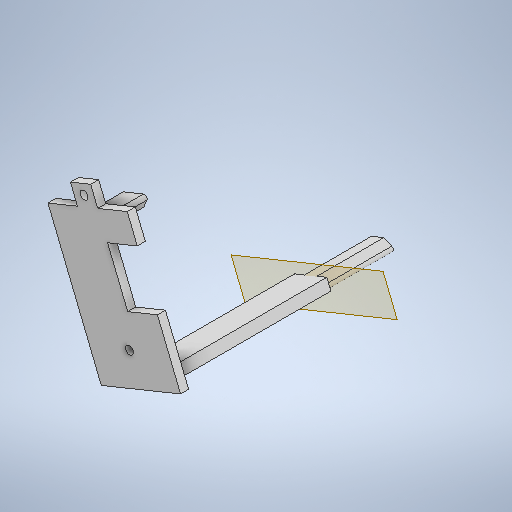
# Autodesk Inventor part: Support_base
Saved by Autodesk Inventor 2025 (Build 290162000, 162)
## iProperties
Created: 2026-10-27
Part Number: Support_base
Material: Generic
Document SubType Name: Modeling
Designer: diego
Density: 1 g/cm^3
Appearance: Default
Author: diego
Autodesk Inventor part; units mm, degrees
ref_plane "YZ Plane" through (0, 0, 0) normal (1, 0, 0) x (0, 1, 0)
ref_plane "XZ Plane" through (0, 0, 0) normal (0, 1, 0) x (-1, 0, 0)
ref_plane "Work Plane1" through (0.6497, -10.1379, 0) normal (0, 0, 1) x (-0.9265, -0.3764, 0)
sketch "Sketch1" plane through (0.6497, -10.1379, 0) normal (0, 0, 1) x (-0.9265, -0.3764, 0)
  line L0 (-4.7946, -9.7818) -> (-7.0875, -7.4889) projected
  arc A0 (-6.3804, -5.7818) -> (-7.0875, -7.4889) centre (-6.3804, -6.7818) ccw projected
  line L1 (-6.3804, -5.7818) -> (1.7912, -5.7818) projected
  arc A1 (2.4983, -7.4889) -> (1.7912, -5.7818) centre (1.7912, -6.7818) ccw projected
  line L2 (2.4983, -7.4889) -> (0.2054, -9.7818) projected
  line L3 (0.2054, -9.7818) -> (27.5974, -9.7818) projected
  line L4 (22.5231, -7.9349) -> (27.5974, -9.7818) projected
  line L5 (22.5231, -7.9349) -> (0.3437, 0.1378) projected
  line L6 (-5.3114, 0) -> (-3.214, 0) projected
  line L7 (-5.3114, 0) -> (-27.1123, -7.9349) projected
  line L8 (-32.1866, -9.7818) -> (-27.1123, -7.9349) projected
  line L9 (-32.1866, -9.7818) -> (-4.7946, -9.7818) projected
  line L10 (-7.0875, -7.4889) -> (-4.7946, -9.7818)
  line L11 (-4.7946, -9.7818) -> (-32.1866, -9.7818)
  line L12 (-32.1866, -9.7818) -> (-27.1123, -7.9349)
  line L13 (-27.1123, -7.9349) -> (-5.3114, 0)
  line L14 (-5.3114, 0) -> (0.7222, 0)
  line L15 (0.7222, 0) -> (22.5231, -7.9349)
  line L16 (22.5231, -7.9349) -> (27.5974, -9.7818)
  line L17 (27.5974, -9.7818) -> (0.2054, -9.7818)
  line L18 (0.2054, -9.7818) -> (2.4983, -7.4889)
  arc A2 (2.4983, -7.4889) -> (1.7912, -5.7818) centre (1.7912, -6.7818) ccw
  line L19 (1.7912, -5.7818) -> (-6.3804, -5.7818)
  arc A3 (-6.3804, -5.7818) -> (-7.0875, -7.4889) centre (-6.3804, -6.7818) ccw
  line L20 (0.2054, -9.7818) -> (-4.7946, -9.7818)
  point P0 (-3.214, -9.6369)
  dimension "d0" = 0
  constraints: 22 end point, 4 point on circle, 2 centre point, 1 horizontal, 11 other
  measures "d0" distance between parallel lines of L0 L10
extrude "Extrusion1" add sketch "Sketch1" along normal blind 65 contours L0 A0 L1 A1 L2 L20
sketch "Sketch3" plane through (0.6497, -10.1379, 0) normal (0, 0, -1) x (0.9265, 0.3764, 0)
  arc A0 (-1.7912, -5.7818) -> (-2.4983, -7.4889) centre (-1.7912, -6.7818) ccw projected
  line L0 (-0.2054, -9.7818) -> (-2.4983, -7.4889) projected
  line L1 (4.7946, -9.7818) -> (-0.2054, -9.7818) projected
  line L2 (7.0875, -7.4889) -> (4.7946, -9.7818) projected
  arc A1 (7.0875, -7.4889) -> (6.3804, -5.7818) centre (6.3804, -6.7818) ccw projected
  line L3 (-1.7912, -5.7818) -> (6.3804, -5.7818) projected
  point P0 (3.214, -9.6369)
extrude "Extrusion2" add sketch "Sketch3" along normal blind 30
sketch "Sketch4" plane through (0.6497, -10.1379, 65) normal (0, 0, 1) x (-0.9265, -0.3764, 0)
  arc A0 (2.4983, -7.4889) -> (1.7912, -5.7818) centre (1.7912, -6.7818) ccw projected
  line L0 (1.7912, -5.7818) -> (-6.3804, -5.7818) projected
  arc A1 (-6.3804, -5.7818) -> (-7.0875, -7.4889) centre (-6.3804, -6.7818) ccw projected
  line L1 (-7.0875, -7.4889) -> (-4.7946, -9.7818) projected
  line L2 (-4.7946, -9.7818) -> (0.2054, -9.7818) projected
  line L3 (0.2054, -9.7818) -> (2.4983, -7.4889) projected
  line L4 (1.7912, -5.7818) -> (-6.3804, -5.7818) projected
  line L5 (-2.2946, -5.7818) -> (-2.2946, -9.7818)
  line L6 (17.7054, -0.7818) -> (-22.2946, -0.7818)
  line L7 (-22.2946, -0.7818) -> (-22.2946, -23.7818)
  line L8 (-22.2946, -23.7818) -> (17.7054, -23.7818)
  line L9 (17.7054, -23.7818) -> (17.7054, -0.7818)
  line L10 (-2.2946, -0.7818) -> (-2.2946, -23.7818) construction
  line L11 (0.2054, -9.7818) -> (-4.7946, -9.7818) projected
  line L12 (-18.2946, -0.7818) -> (13.7054, -0.7818)
  line L13 (-18.2946, -0.7818) -> (-18.2946, -15.7818) construction
  line L14 (-18.2946, -15.7818) -> (-22.2946, -15.7818)
  line L15 (-18.2946, -0.7818) -> (-22.2946, -15.7818)
  line L16 (13.7054, -0.7818) -> (17.7054, -15.7818)
  point P0 (-3.214, -9.6369)
  point P1 (-2.2946, -9.7818)
  point P2 (17.7054, -15.7818)
  point P3 (13.7054, -0.7818)
  point P4 (-18.2946, -0.7818)
  dimension "d5" = 40
  dimension "d6" = 5
  dimension "d13" = 14
  dimension "d14" = 32
  dimension "d15" = 15
  constraints: 22 end point, 6 midpoint, 2 horizontal, 2 parallel, 2 perpendicular, 2 point on line, 1 symmetric about line, 1 vertical
  measures "d5" distance of L8.end L7.end
  measures "d6" distance between parallel lines of L0 L6
  measures "d13" distance between parallel lines of L8 L2
  measures "d14" distance of L12.start L12.end
  measures "d15" distance of L12.start L13.end
extrude "Extrusion3" add sketch "Sketch4" against normal blind 3 contours L16 L9 L8 L7 L15 L6
sketch "Sketch5" plane through (0.6497, -10.1379, 62) normal (0, 0, -1) x (0.9265, 0.3764, 0)
  line L0 (22.2946, -23.7818) -> (22.2946, -15.7818) projected
  line L1 (18.2946, -0.7818) -> (-13.7054, -0.7818) projected
  line L2 (-17.7054, -15.7818) -> (-17.7054, -23.7818) projected
  line L3 (-17.7054, -23.7818) -> (22.2946, -23.7818) projected
  arc A0 (-1.7912, -5.7818) -> (-2.4983, -7.4889) centre (-1.7912, -6.7818) ccw projected
  line L4 (6.3804, -5.7818) -> (-1.7912, -5.7818) projected
  arc A1 (7.0875, -7.4889) -> (6.3804, -5.7818) centre (6.3804, -6.7818) ccw projected
  line L5 (4.7946, -9.7818) -> (7.0875, -7.4889) projected
  line L6 (-0.2054, -9.7818) -> (4.7946, -9.7818) projected
  line L7 (-2.4983, -7.4889) -> (-0.2054, -9.7818) projected
  line L8 (-4.2054, -5.7818) -> (8.7946, -5.7818)
  line L9 (8.7946, -5.7818) -> (8.7946, -9.7818)
  line L10 (8.7946, -9.7818) -> (-4.2054, -9.7818)
  line L11 (-4.2054, -9.7818) -> (-4.2054, -5.7818)
  line L12 (-4.2054, -5.7818) -> (8.7946, -9.7818) construction
  line L13 (8.7946, -5.7818) -> (-4.2054, -9.7818) construction
  line L14 (-2.4983, -7.4889) -> (-0.2054, -9.7818) projected
  line L15 (-0.2054, -9.7818) -> (-4.2054, -5.7818)
  line L16 (4.7946, -9.7818) -> (8.7946, -5.7818)
  line L17 (22.2946, -15.7818) -> (18.2946, -0.7818) projected
  line L18 (-13.7054, -0.7818) -> (-17.7054, -15.7818) projected
  point P0 (3.214, -9.6369)
  point P1 (2.2946, -7.7818)
  point P2 (2.2946, -9.7818)
  point P3 (2.2946, -5.7818)
  point P4 (-0.2054, -9.7818)
  point P5 (4.7946, -9.7818)
  point P6 (6.3804, -5.7818)
  point P7 (-1.7912, -5.7818)
  constraints: 16 end point, 6 midpoint, 5 point on line, 2 parallel, 1 horizontal, 1 perpendicular, 1 tangent
ref_plane "Work Plane2" through (-30.1843, -12.7613, 0) normal (0, 0, 1) x (1, 0, 0)
extrude "Extrusion4" add sketch "Sketch5" along normal up to surface (62 mm away) contours L4 A1 L5 L6 L7 A0 | A0 L15 L8 | L7 L10 L11 L15 | L8 L16 A1 | L16 L9 L10 L5
sketch "Sketch6" plane through (0.6497, -10.1379, -30) normal (0, 0, -1) x (0.9265, 0.3764, 0)
  line L0 (6.3804, -5.7818) -> (-1.7912, -5.7818) projected
  arc A0 (-1.7912, -5.7818) -> (-2.4983, -7.4889) centre (-1.7912, -6.7818) ccw projected
  line L1 (-2.4983, -7.4889) -> (-0.2054, -9.7818) projected
  line L2 (-0.2054, -9.7818) -> (4.7946, -9.7818) projected
  line L3 (4.7946, -9.7818) -> (7.0875, -7.4889) projected
  arc A1 (7.0875, -7.4889) -> (6.3804, -5.7818) centre (6.3804, -6.7818) ccw projected
  point P0 (3.214, -9.6369)
extrude "Extrusion5" cut sketch "Sketch6" against normal blind 5
sketch "Sketch7" plane through (0.6497, -10.1379, 62) normal (0, 0, -1) x (0.9265, 0.3764, 0)
  line L0 (8.7946, -9.7818) -> (-4.2054, -9.7818) projected
  line L1 (-1.7912, -5.7818) -> (6.3804, -5.7818) projected
  line L2 (8.7946, -5.7818) -> (6.3804, -5.7818) projected
  line L3 (8.7946, -5.7818) -> (-4.2054, -5.7818) projected
  line L4 (-1.7912, -5.7818) -> (-4.2054, -5.7818) projected
  line L5 (8.7946, -5.7818) -> (-4.2054, -5.7818) projected
  line L6 (8.7946, -5.7818) -> (8.7946, -9.7818) projected
  line L7 (8.7946, -9.7818) -> (-4.2054, -9.7818) projected
  line L8 (-4.2054, -9.7818) -> (-4.2054, -5.7818) projected
  line L9 (-17.7054, -15.7818) -> (-17.7054, -23.7818) projected
  line L10 (-17.7054, -23.7818) -> (22.2946, -23.7818) projected
  line L11 (22.2946, -23.7818) -> (22.2946, -15.7818) projected
  line L12 (22.2946, -15.7818) -> (18.2946, -0.7818) projected
  line L13 (18.2946, -0.7818) -> (-13.7054, -0.7818) projected
  line L14 (-13.7054, -0.7818) -> (-17.7054, -15.7818) projected
  line L15 (-4.2054, -5.7818) -> (8.7946, -5.7818)
  line L16 (8.7946, -5.7818) -> (8.7946, -0.7818)
  line L17 (8.7946, -0.7818) -> (-4.2054, -0.7818)
  line L18 (-4.2054, -0.7818) -> (-4.2054, -5.7818)
  line L19 (5.8653, -0.7818) -> (-1.2761, -0.7818)
  line L20 (-1.2761, -5.7818) -> (5.8653, -5.7818)
  line L21 (2.2946, -0.7818) -> (2.2946, -5.7818)
  line L22 (-1.2054, -0.7818) -> (5.7946, -0.7818)
  line L23 (5.7946, -0.7818) -> (5.7946, -5.7818)
  line L24 (5.7946, -5.7818) -> (-1.2054, -5.7818)
  line L25 (-1.2054, -5.7818) -> (-1.2054, -0.7818)
  line L26 (-1.2054, -0.7818) -> (5.7946, -5.7818) construction
  line L27 (5.7946, -0.7818) -> (-1.2054, -5.7818) construction
  point P0 (3.214, -9.6369)
  point P1 (2.2946, -3.2818)
  point P2 (5.7946, -0.7818)
  point P3 (5.7946, -5.7818)
  point P4 (6.3804, -5.7818)
  point P5 (-1.2054, -5.7818)
  point P6 (-1.2054, -0.7818)
  point P7 (-4.2054, -0.7818)
  point P8 (-4.2054, -5.7818)
  point P9 (-1.7912, -5.7818)
  dimension "d16" = 3
  constraints: 26 end point, 6 midpoint, 6 point on line, 5 parallel, 3 horizontal, 2 perpendicular, 1 vertical
  measures "d16" distance between parallel lines of L23 L16
extrude "Extrusion6" add sketch "Sketch7" along normal blind 5 contours L2 L1 L23 L13 L16 | L18 L13 L25 L1 L3
sketch "Sketch8" plane through (-6.9283, -2.6585, 62) normal (-0.9265, -0.3764, 0) x (0, 0, -1)
  line L0 (62, 4) -> (62, 0) projected
  line L1 (5, 4) -> (62, 4) projected
  line L2 (5, 9) -> (5, 4) projected
  line L3 (0, 9) -> (5, 9) projected
  line L4 (0, 0) -> (0, 9) projected
  line L5 (0, 0) -> (62, 0) projected
  line L6 (5, 4) -> (0, 9)
  point P0 (62, 0.1449)
  constraints: 2 end point
extrude "Extrusion7" cut sketch "Sketch8" against normal through all contours L6 L3 L2
sketch "Sketch9" plane through (0.6497, -10.1379, 65) normal (0, 0, 1) x (-0.9265, -0.3764, 0)
  line L0 (17.7054, -23.7818) -> (17.7054, -15.7818) projected
  line L1 (17.7054, -15.7818) -> (13.7054, -0.7818) projected
  line L2 (13.7054, -0.7818) -> (-18.2946, -0.7818) projected
  line L3 (-18.2946, -0.7818) -> (-22.2946, -15.7818) projected
  line L4 (-22.2946, -15.7818) -> (-22.2946, -23.7818) projected
  line L5 (-22.2946, -23.7818) -> (17.7054, -23.7818) projected
  line L6 (13.7054, -0.7818) -> (13.7054, -23.7818)
  line L7 (-18.2946, -0.7818) -> (-18.2946, -23.7818)
  point P0 (-3.214, -9.6369)
  constraints: 4 end point, 2 point on line, 1 perpendicular, 1 vertical
extrude "Extrusion8" cut sketch "Sketch9" against normal blind 65 contours L5 L6 L1 L0 | L5 L4 L3 L7
sketch "Sketch10" plane through (0.6497, -10.1379, 65) normal (0, 0, 1) x (0.9265, 0.3764, 0)
  line L0 (5.7946, 5.7818) -> (5.7946, 0.7818) construction
  line L1 (5.7946, 0.7818) -> (-1.2054, 0.7818) construction
  line L2 (-1.2054, 0.7818) -> (-1.2054, 5.7818) construction
  line L3 (5.7946, 5.7818) -> (-1.2054, 5.7818) construction
  line L4 (5.7946, 5.7818) -> (-1.2054, 5.7818) construction
  line L5 (-1.2054, 5.7818) -> (-4.2054, 5.7818) construction
  line L6 (-1.7912, 5.7818) -> (-4.2054, 5.7818) construction
  line L7 (-1.7912, 5.7818) -> (6.3804, 5.7818) construction
  line L8 (8.7946, 5.7818) -> (6.3804, 5.7818) construction
  line L9 (8.7946, 5.7818) -> (5.7946, 5.7818) construction
  line L10 (18.2946, 23.7818) -> (18.2946, 0.7818) construction
  line L11 (18.2946, 0.7818) -> (8.7946, 0.7818) construction
  line L12 (8.7946, 0.7818) -> (8.7946, 9.7818) construction
  line L13 (8.7946, 9.7818) -> (-4.2054, 9.7818) construction
  line L14 (-4.2054, 9.7818) -> (-4.2054, 0.7818) construction
  line L15 (-4.2054, 0.7818) -> (-13.7054, 0.7818) construction
  line L16 (-13.7054, 0.7818) -> (-13.7054, 23.7818) construction
  line L17 (-13.7054, 23.7818) -> (18.2946, 23.7818) construction
  line L18 (8.7946, 5.7818) -> (18.2946, 5.7818) construction
  line L19 (-4.2054, 5.7818) -> (-13.7054, 5.7818) construction
  line L20 (18.2946, 0.7818) -> (18.2946, 23.7818) projected
  line L21 (18.2946, 23.7818) -> (-13.7054, 23.7818) projected
  line L22 (-13.7054, 23.7818) -> (-13.7054, 0.7818) projected
  line L23 (-13.7054, 0.7818) -> (18.2946, 0.7818) projected
  line L24 (18.2946, 5.7818) -> (-13.7054, 5.7818)
  point P0 (3.214, 9.6369)
  point P1 (18.2946, 5.7818)
  point P2 (-13.7054, 5.7818)
  constraints: 6 end point, 3 point on line, 1 collinear, 1 perpendicular
extrude "Extrusion9" cut sketch "Sketch10" against normal blind 65 contours L23 L22 L24 L20
sketch "Sketch12" plane through (0.6497, -10.1379, 65) normal (0, 0, 1) x (0.9265, 0.3764, 0)
  line L0 (-13.7054, 5.7818) -> (18.2946, 5.7818) projected
  line L1 (18.2946, 5.7818) -> (18.2946, 23.7818) projected
  line L2 (18.2946, 23.7818) -> (-13.7054, 23.7818) projected
  line L3 (-13.7054, 23.7818) -> (-13.7054, 5.7818) projected
  line L4 (-13.7054, 14.7818) -> (18.2946, 14.7818) construction
  line L5 (18.2946, 23.7818) -> (18.2946, 5.7818) projected
  line L6 (-13.7054, 5.7818) -> (18.2946, 5.7818) projected
  line L7 (2.2946, 5.7818) -> (2.2946, 23.7818) construction
  line L8 (2.2946, 5.7818) -> (2.2946, 53.7818) construction
  line L9 (18.2946, 5.7818) -> (-13.7054, 5.7818)
  line L10 (-13.7054, 5.7818) -> (-13.7054, 53.7818)
  line L11 (-13.7054, 53.7818) -> (18.2946, 53.7818)
  line L12 (18.2946, 53.7818) -> (18.2946, 5.7818)
  line L13 (-13.7054, 53.7818) -> (18.2946, 53.7818)
  line L14 (18.2946, 53.7818) -> (18.2946, 58.7818)
  line L15 (18.2946, 58.7818) -> (-13.7054, 58.7818)
  line L16 (-13.7054, 58.7818) -> (-13.7054, 53.7818)
  dimension "d25" = 48
  dimension "d26" = 5
  constraints: 22 end point, 5 midpoint, 5 parallel, 2 horizontal, 2 perpendicular, 1 point on line, 1 vertical
  measures "d25" distance of L7.start L8.end
  measures "d26" distance of L15.end L10.end
extrude "Extrusion10" add sketch "Sketch12" against normal up to surface (3 mm away) contours L10 L11 L12 L2 | L16 L15 L14 L11
sketch "Sketch13" plane through (0.6497, -10.1379, 62) normal (0, 0, -1) x (-0.9265, -0.3764, 0)
  line L0 (4.2054, 5.7818) -> (13.7054, 5.7818) projected
  line L1 (13.7054, 5.7818) -> (13.7054, 58.7818) projected
  line L2 (13.7054, 58.7818) -> (-18.2946, 58.7818) projected
  line L3 (-18.2946, 58.7818) -> (-18.2946, 5.7818) projected
  line L4 (-18.2946, 5.7818) -> (-8.7946, 5.7818) projected
  line L5 (-8.7946, 5.7818) -> (-8.7946, 9.7818) projected
  line L6 (-8.7946, 9.7818) -> (4.2054, 9.7818) projected
  line L7 (4.2054, 9.7818) -> (4.2054, 5.7818) projected
  line L8 (-18.2946, 58.7818) -> (13.7054, 58.7818)
  line L9 (13.7054, 58.7818) -> (13.7054, 55.7818)
  line L10 (1.7912, 55.7818) -> (-18.2946, 55.7818)
  line L11 (-18.2946, 55.7818) -> (-18.2946, 58.7818)
  line L12 (-18.2946, 55.7818) -> (13.7054, 55.7818)
  line L13 (13.7054, 55.7818) -> (13.7054, 51.7818)
  line L14 (13.7054, 51.7818) -> (-18.2946, 51.7818)
  line L15 (-18.2946, 51.7818) -> (-18.2946, 55.7818)
  line L16 (-2.2946, 51.7818) -> (-2.2946, 58.7818) construction
  line L17 (0.2054, 51.7818) -> (-4.7946, 51.7818)
  line L18 (-4.7946, 51.7818) -> (-4.7946, 55.7818)
  line L19 (-4.7946, 55.7818) -> (0.2054, 55.7818)
  line L20 (0.2054, 55.7818) -> (0.2054, 51.7818)
  line L21 (0.2054, 51.7818) -> (-4.7946, 55.7818) construction
  line L22 (-4.7946, 51.7818) -> (0.2054, 55.7818) construction
  line L23 (-4.7946, 51.7818) -> (-7.0875, 54.0747)
  line L24 (-4.7946, 51.7818) -> (-1.552, 51.7818) construction
  line L25 (0.2054, 51.7818) -> (2.4983, 54.0747)
  line L26 (0.2054, 51.7818) -> (3.448, 51.7818) construction
  line L27 (-6.3804, 55.7818) -> (4.2054, 55.7818)
  arc A0 (-6.3804, 55.7818) -> (-7.0875, 54.0747) centre (-6.3804, 54.7818) ccw
  arc A1 (2.4983, 54.0747) -> (1.7912, 55.7818) centre (1.7912, 54.7818) ccw
  point P0 (-3.214, 9.6369)
  point P1 (-2.2946, 53.7818)
  point P2 (-8.7946, 55.7818)
  point P3 (-4.7946, 51.7818)
  point P4 (0.2054, 51.7818)
  dimension "d29" = 3
  dimension "d30" = 4
  dimension "d31" = 5
  dimension "d32" = 2
  dimension "d33" = 135
  dimension "d34" = 45
  dimension "d35" = 1
  constraints: 40 end point, 11 point on line, 6 parallel, 5 horizontal, 5 midpoint, 4 perpendicular, 4 point on circle, 4 tangent, 2 centre point, 2 equal length, 1 collinear, 1 equal radius
  measures "d29" distance between parallel lines of L2 L10
  measures "d30" distance between parallel lines of L10 L14
  measures "d31" distance of L18.end L19.end
  measures "d32" distance from line of L10 point (-2.295, 53.782)
  measures "d33" angle of L24 L23
  measures "d34" angle of L26 L25
  measures "d35" radius of A0
extrude "Extrusion11" add sketch "Sketch13" along normal blind 13 contours L14 L18 L10 L20 | L20 L10 A1 L25 | L23 A0 L10 L18
sketch "Sketch14" plane through (0.6497, -10.1379, 62) normal (0, 0, -1) x (-0.9265, -0.3764, 0)
  arc A0 (2.4983, 54.0747) -> (1.7912, 55.7818) centre (1.7912, 54.7818) ccw projected
  line L0 (2.4983, 54.0747) -> (0.2054, 51.7818) projected
  line L1 (0.2054, 51.7818) -> (-4.7946, 51.7818) projected
  line L2 (-4.7946, 51.7818) -> (-7.0875, 54.0747) projected
  arc A1 (-6.3804, 55.7818) -> (-7.0875, 54.0747) centre (-6.3804, 54.7818) ccw projected
  line L3 (-6.3804, 55.7818) -> (1.7912, 55.7818) projected
  line L4 (4.2054, 5.7818) -> (13.7054, 5.7818) projected
  line L5 (13.7054, 5.7818) -> (13.7054, 58.7818) projected
  line L6 (13.7054, 58.7818) -> (-18.2946, 58.7818) projected
  line L7 (-18.2946, 58.7818) -> (-18.2946, 5.7818) projected
  line L8 (-18.2946, 5.7818) -> (-8.7946, 5.7818) projected
  line L9 (-8.7946, 5.7818) -> (-8.7946, 9.7818) projected
  line L10 (-8.7946, 9.7818) -> (4.2054, 9.7818) projected
  line L11 (4.2054, 9.7818) -> (4.2054, 5.7818) projected
  line L12 (1.7912, 5.7818) -> (-6.3804, 5.7818) projected
  line L13 (-2.2946, 5.7818) -> (-2.2946, 65.7818) construction
  line L14 (-6.3804, 55.7818) -> (1.7912, 55.7818)
  line L15 (1.7912, 55.7818) -> (1.7912, 65.7818)
  line L16 (1.7912, 65.7818) -> (-6.3804, 65.7818)
  line L17 (-6.3804, 65.7818) -> (-6.3804, 55.7818)
  point P0 (-3.214, 9.6369)
  point P1 (-6.3804, 58.7818)
  point P2 (1.7912, 58.7818)
  dimension "d38" = 60
  constraints: 10 end point, 3 point on line, 2 midpoint, 2 parallel, 1 horizontal, 1 perpendicular, 1 vertical
  measures "d38" distance of L13.start L13.end
extrude "Extrusion12" add sketch "Sketch14" against normal up to surface (3 mm away) contours L6 L17 L16 L15
sketch "Sketch15" plane through (0.6497, -10.1379, 62) normal (0, 0, -1) x (-0.9265, -0.3764, 0)
  arc A0 (2.4983, 54.0747) -> (1.7912, 55.7818) centre (1.7912, 54.7818) ccw projected
  line L0 (2.4983, 54.0747) -> (0.2054, 51.7818) projected
  line L1 (0.2054, 51.7818) -> (-4.7946, 51.7818) projected
  line L2 (-4.7946, 51.7818) -> (-7.0875, 54.0747) projected
  arc A1 (-6.3804, 55.7818) -> (-7.0875, 54.0747) centre (-6.3804, 54.7818) ccw projected
  line L3 (-6.3804, 55.7818) -> (1.7912, 55.7818) projected
  line L4 (4.2054, 5.7818) -> (13.7054, 5.7818) projected
  line L5 (13.7054, 5.7818) -> (13.7054, 58.7818) projected
  line L6 (13.7054, 58.7818) -> (1.7912, 58.7818) projected
  line L7 (1.7912, 58.7818) -> (1.7912, 65.7818) projected
  line L8 (1.7912, 65.7818) -> (-6.3804, 65.7818) projected
  line L9 (-6.3804, 65.7818) -> (-6.3804, 58.7818) projected
  line L10 (-6.3804, 58.7818) -> (-18.2946, 58.7818) projected
  line L11 (-18.2946, 58.7818) -> (-18.2946, 5.7818) projected
  line L12 (-18.2946, 5.7818) -> (-8.7946, 5.7818) projected
  line L13 (-8.7946, 5.7818) -> (-8.7946, 9.7818) projected
  line L14 (-8.7946, 9.7818) -> (4.2054, 9.7818) projected
  line L15 (4.2054, 9.7818) -> (4.2054, 5.7818) projected
  line L16 (-2.2946, 65.7818) -> (-2.2946, 5.7818) construction
  line L17 (13.7054, 5.7818) -> (-18.2946, 5.7818) projected
  circle A2 centre (-2.2946, 62.2818) radius 1.5
  circle A3 centre (-2.2946, 17.2818) radius 1.5
  line L18 (-6.3804, 58.7818) -> (1.7912, 65.7818) construction
  line L19 (-6.3804, 65.7818) -> (1.7912, 58.7818) construction
  point P0 (-3.214, 9.6369)
  dimension "d41" = 3
  dimension "d42" = 3
  dimension "d43" = 45
  constraints: 6 end point, 3 midpoint, 2 centre point, 2 point on line
  measures "d41" diameter of A2
  measures "d42" diameter of A3
  measures "d43" distance of A2.centre A3.centre
extrude "Extrusion13" cut sketch "Sketch15" against normal blind 10 contours A2 | A3
sketch "Sketch16" plane through (0.6497, -10.1379, 62) normal (0, 0, -1) x (-0.9265, -0.3764, 0)
  circle A0 centre (-2.2946, 62.2818) radius 1.5 projected
  circle A1 centre (-2.2946, 17.2818) radius 1.5 projected
  arc A2 (2.4983, 54.0747) -> (1.7912, 55.7818) centre (1.7912, 54.7818) ccw projected
  line L0 (2.4983, 54.0747) -> (0.2054, 51.7818) projected
  line L1 (0.2054, 51.7818) -> (-4.7946, 51.7818) projected
  line L2 (-4.7946, 51.7818) -> (-7.0875, 54.0747) projected
  arc A3 (-6.3804, 55.7818) -> (-7.0875, 54.0747) centre (-6.3804, 54.7818) ccw projected
  line L3 (-6.3804, 55.7818) -> (1.7912, 55.7818) projected
  line L4 (4.2054, 5.7818) -> (13.7054, 5.7818) projected
  line L5 (13.7054, 5.7818) -> (13.7054, 58.7818) projected
  line L6 (13.7054, 58.7818) -> (1.7912, 58.7818) projected
  line L7 (1.7912, 58.7818) -> (1.7912, 65.7818) projected
  line L8 (1.7912, 65.7818) -> (-6.3804, 65.7818) projected
  line L9 (-6.3804, 65.7818) -> (-6.3804, 58.7818) projected
  line L10 (-6.3804, 58.7818) -> (-18.2946, 58.7818) projected
  line L11 (-18.2946, 58.7818) -> (-18.2946, 5.7818) projected
  line L12 (-18.2946, 5.7818) -> (-8.7946, 5.7818) projected
  line L13 (-8.7946, 5.7818) -> (-8.7946, 9.7818) projected
  line L14 (-8.7946, 9.7818) -> (4.2054, 9.7818) projected
  line L15 (4.2054, 9.7818) -> (4.2054, 5.7818) projected
  line L16 (0.2054, 51.7818) -> (-4.7946, 51.7818) projected
  line L17 (-2.2946, 51.7818) -> (-2.2946, 9.7818) construction
  line L18 (-18.2946, 58.7818) -> (-18.2946, 5.7818) projected
  line L19 (-18.2946, 48.7818) -> (-6.2946, 48.7818)
  line L20 (-6.2946, 48.7818) -> (-6.2946, 28.7818)
  line L21 (-6.2946, 28.7818) -> (-18.2946, 28.7818)
  point P0 (-3.214, 9.6369)
  dimension "d46" = 20
  dimension "d47" = 10
  dimension "d48" = 20
  constraints: 8 end point, 2 midpoint, 2 perpendicular, 2 point on line, 1 horizontal
  measures "d46" distance between parallel lines of L21 L19
  measures "d47" distance between parallel lines of L10 L19
  measures "d48" distance between parallel lines of L5 L20
extrude "Extrusion14" cut sketch "Sketch16" against normal through all contours L11 L19 L20 L21
body "Solid1"
